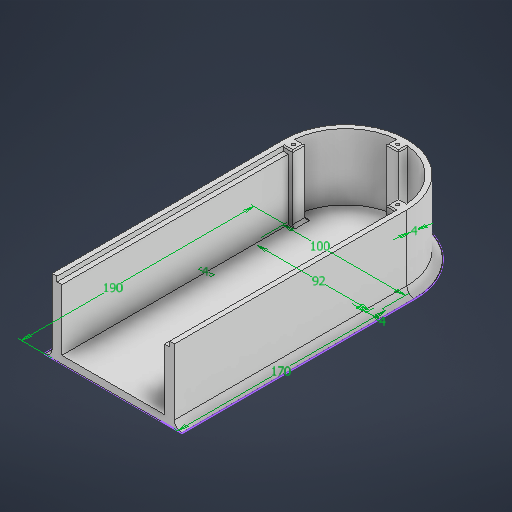
# Autodesk Inventor part: modificacao_manipulador_base
Saved by Autodesk Inventor 2027.1 (Build 311270010, 270A)
## iProperties
Created: 2026-11-03
Part Number: modificacao_manipulador_base
Material: Genérico
Document SubType Name: Modeling
Designer: Evellyn
Density: 1 g/cm^3
Appearance: Padrão
Author: Evellyn
Autodesk Inventor part; units mm, degrees
ref_plane "YZ Plane" through (0, 0, 0) normal (1, 0, 0) x (0, 1, 0)
ref_plane "XZ Plane" through (0, 0, 0) normal (0, 1, 0) x (-1, 0, 0)
ref_plane "XY Plane" through (0, 0, 0) normal (0, 0, 1) x (1, 0, 0)
sketch "Esboço1" plane through (0, 0, 0) normal (0, 1, 0) x (-1, 0, 0)
  line L0 (50.2572, -105.0579) -> (50.2572, 84.9421)
  line L1 (50.2572, 84.9421) -> (-49.7428, 84.9421)
  line L2 (-49.7428, 84.9421) -> (-49.7428, -105.0579)
  line L3 (-49.7428, -85.0579) -> (50.2572, 84.9421) construction
  line L4 (50.2572, -85.0579) -> (-49.7428, 84.9421) construction
  line L5 (50.2572, 0.9229) -> (-49.7428, 0.9229)
  line L6 (-49.7428, 0.9229) -> (-49.7428, -105.0579)
  line L7 (50.2572, -105.0579) -> (50.2572, 0.9229)
  line L8 (0.2572, -0.0579) -> (0.2572, -55.0579)
  arc A0 (-49.7428, -105.0579) -> (50.2572, -105.0579) centre (0.2572, -105.0579) ccw
  line L9 (46.2572, 84.9421) -> (46.2572, -105.0579)
  line L10 (-45.7428, 84.9421) -> (-45.7428, -105.0579)
  arc A1 (-45.7428, -105.0579) -> (46.2572, -105.0579) centre (0.2572, -105.0579) ccw
  line L11 (56.5116, 84.9421) -> (56.5116, -105.0579)
  arc A2 (-55.9972, -105.0579) -> (56.5116, -105.0579) centre (0.2572, -105.0579) ccw
  line L12 (-55.9972, -105.0579) -> (-55.9972, 84.9421)
  line L13 (56.5116, 84.9421) -> (50.2572, 84.9421)
  line L14 (-49.7428, 84.9421) -> (-55.9972, 84.9421)
  dimension "d16" = 170
  dimension "d17" = 100
  dimension "d18" = 4
  dimension "d19" = 190
  dimension "d20" = 4
  dimension "d21" = 4
  dimension "d22" = 92
  constraints: 30 end point, 7 point on circle, 4 point on line, 3 centre point, 3 equal length, 2 horizontal, 2 midpoint, 1 concentric, 1 perpendicular, 1 tangent, 1 vertical, 2 other
  measures "d16" distance of L2.start L3.start
  measures "d17" distance of L3.start L4.start
  measures "d18" distance between parallel lines of L9 L0
  measures "d19" distance of L7.start L0.end
  measures "d20" distance between parallel lines of L6 L10
  measures "d21" radial gap between concentric circles of A1 A0
  measures "d22" distance between parallel lines of L10 L9
extrude "Extrusão1" add sketch "Esboço1" along normal blind 6 contours L9 A1 L10 L5 | L5 L10 L1 L9
extrude "Extrusão2" add sketch "Esboço1" along normal blind 60 contours A0 L2 L5 L10 A1 L9 L0 | L5 L9 L1 L0 | L2 L1 L10 L5
sketch "Esboço2" plane through (0, 6, 0) normal (0, 1, 0) x (1, 0, 0)
  arc A0 (49.7428, 105.0579) -> (-50.2572, 105.0579) centre (-0.2572, 105.0579) ccw projected
  arc A1 (45.7428, 105.0579) -> (-46.2572, 105.0579) centre (-0.2572, 105.0579) ccw projected
  circle A2 centre (-0.2572, 105.0579) radius 48.2336
  line L0 (-0.2572, 155.0579) -> (-0.2572, 49.8481)
  line L1 (-57.3104, 105.0579) -> (74.0886, 105.0579)
  line L2 (45.7428, -84.9421) -> (45.7428, 105.0579) projected
  arc A3 (45.7428, 105.0579) -> (-46.2572, 105.0579) centre (-0.2572, 105.0579) ccw projected
  line L3 (-46.2572, 105.0579) -> (-46.2572, -84.9421) projected
  line L4 (-46.2572, -84.9421) -> (45.7428, -84.9421) projected
  line L5 (4.7428, 153.2919) -> (-5.2572, 153.2919)
  line L6 (-5.2572, 153.2919) -> (-5.2572, 143.2919)
  line L7 (-5.2572, 143.2919) -> (4.7428, 143.2919)
  line L8 (4.7428, 143.2919) -> (4.7428, 153.2919)
  line L9 (4.7428, 153.2919) -> (-5.2572, 143.2919) construction
  line L10 (-5.2572, 153.2919) -> (4.7428, 143.2919) construction
  line L11 (-38.4912, 100.0579) -> (-38.4912, 110.0579)
  line L12 (-48.4912, 100.0579) -> (-38.4912, 100.0579)
  line L13 (-38.4912, 110.0579) -> (-48.4912, 110.0579)
  line L14 (-48.4912, 110.0579) -> (-48.4912, 100.0579)
  line L15 (37.9768, 110.0579) -> (37.9768, 100.0579)
  line L16 (47.9768, 110.0579) -> (37.9768, 110.0579)
  line L17 (37.9768, 100.0579) -> (47.9768, 100.0579)
  line L18 (47.9768, 100.0579) -> (47.9768, 110.0579)
  point P0 (0, 0)
  point P1 (-0.2572, 148.2919)
  point P2 (45.4702, 110.0579)
  point P3 (45.7428, 100.0579)
  point P4 (45.7428, 105.0579)
  point P5 (-45.9847, 110.0579)
  point P6 (-46.2572, 105.0579)
  point P7 (-46.2572, 100.0579)
  point P8 (4.7428, 150.7853)
  point P9 (-5.2572, 150.7853)
  dimension "d27" = 96.4673
  dimension "d32" = 10
  dimension "d33" = 10
  dimension "d34" = 38.234
  dimension "d37" = 180
  constraints: 32 end point, 2 coincident, 2 horizontal, 2 midpoint, 2 parallel, 2 point on line, 1 centre point, 1 perpendicular, 1 point on circle, 1 vertical, 17 other
  measures "d27" diameter of A2
  measures "d32" distance of L7.end L6.end
  measures "d33" distance of L6.end L5.end
  measures "d34" distance from line of A0.centre L7
extrude "Extrusão3" add sketch "Esboço2" along normal blind 54 contours L1 L15 L16 A1 | L2 L17 L15 L1 | L0 L7 L6 A1 | A1 L8 L7 L0 | A1 L13 L11 L1 | L1 L11 L12 L3
fillet "Arredondamento1" radius 1 9 edges at (-5.2572, 60, -147.0386) (4.7428, 60, -147.0386) (-0.2572, 60, -143.2919) (41.8598, 60, -100.0579) (37.9768, 60, -105.0579) (41.7235, 60, -110.0579) (-42.2379, 60, -110.0579) (-42.3742, 60, -100.0579) (-38.4912, 60, -105.0579)
fillet "Arredondamento da face2" radius 2 1 edges at (-38.4912, 6, -105.0579)
fillet "Arredondamento da face3" radius 2 2 edges at (-37.4912, 6, -110.0579) (-42.2379, 6, -110.0579)
fillet "Arredondamento da face4" radius 2 1 edges at (-0.2572, 6, -143.2919)
fillet "Arredondamento da face5" radius 2 2 edges at (4.7428, 6, -142.2919) (4.7428, 6, -147.0386)
fillet "Arredondamento da face6" radius 2 2 edges at (-5.2572, 6, -142.2919) (-5.2572, 6, -147.0386)
fillet "Arredondamento da face7" radius 2 1 edges at (37.9768, 6, -105.0579)
sketch "Esboço3" plane through (0, 6, 0) normal (0, 1, 0) x (1, 0, 0)
  line L0 (-42.2572, 78.0579) -> (-42.2572, -84.9421)
  line L1 (-46.2572, -84.9421) -> (45.7428, -84.9421) projected
  line L2 (-46.2572, -84.9421) -> (-46.2572, 101.0579) projected
  line L3 (37.9768, 100.0579) -> (45.7428, 100.0579) projected
  line L4 (45.7428, 101.0579) -> (45.7428, -84.9421) projected
  line L5 (41.7428, 79.7413) -> (41.7428, -84.9421)
  line L6 (41.7428, 79.7413) -> (41.7428, 100.0579)
  line L7 (-42.2572, 78.0579) -> (-42.2572, 100.0579)
  line L8 (-46.2572, 100.0579) -> (-38.4912, 100.0579) projected
  point P0 (0, 0)
  dimension "d49" = 4
  dimension "d51" = 4
  constraints: 8 end point, 4 point on line, 2 perpendicular, 2 vertical
  measures "d49" distance between parallel lines of L2 L0
  measures "d51" distance between parallel lines of L5 L4
extrude "Extrusão4" add sketch "Esboço3" along normal blind 50
sketch "Esboço4" plane through (0, 60, 0) normal (0, 1, 0) x (1, 0, 0)
  arc A0 (-4.2572, 150.8836) -> (-46.083, 109.0579) centre (-0.2572, 105.0579) ccw projected
  line L0 (-46.083, 109.0579) -> (-39.4912, 109.0579) projected
  line L1 (-39.4912, 109.0579) -> (-39.4912, 101.0579) projected
  line L2 (-39.4912, 101.0579) -> (-46.2572, 101.0579) projected
  line L3 (38.9768, 109.0579) -> (45.5685, 109.0579) projected
  line L4 (38.9768, 101.0579) -> (38.9768, 109.0579) projected
  line L5 (45.7428, 101.0579) -> (38.9768, 101.0579) projected
  arc A1 (45.5685, 109.0579) -> (3.7428, 150.8836) centre (-0.2572, 105.0579) ccw projected
  arc A2 (49.7428, 105.0579) -> (-50.2572, 105.0579) centre (-0.2572, 105.0579) ccw projected
  circle A3 centre (-0.2572, 105.0579) radius 42.5494
  circle A4 centre (-0.2572, 147.6073) radius 1.35
  circle A5 centre (-42.8066, 105.0579) radius 1.35
  circle A6 centre (42.2922, 105.0579) radius 1.35
  point P0 (0, 0)
  dimension "d54" = 85.0988
  dimension "d55" = 2.7
  dimension "d58" = 180
  dimension "d77" = 42.5494
  constraints: 3 centre point, 1 coincident, 1 vertical alignment, 7 other
  measures "d55" diameter of A4
  measures "d77" horizontal distance of A4.centre A6.centre
extrude "Extrusão5" cut sketch "Esboço4" against normal blind 8 contours A4 A3 | A3 A4 | A5 A3 | A3 A5 | A6 A3 | A3 A6
extrude "Extrusão6" add sketch "Esboço1" along normal blind 0.2 contours L0 L13 L11 A2 L12 L14 L2 A0
fillet "Arredondamento da face8" radius 6 1 edges at (49.7428, 0.2, -10.0579)
sketch "Esboço5" plane through (0, 56, 0) normal (0, 1, 0) x (1, 0, 0)
  line L0 (41.7428, -84.9421) -> (45.7428, -84.9421) projected
  line L1 (41.7428, -84.9421) -> (45.7428, -84.9421)
  line L2 (45.7428, -84.9421) -> (45.7428, -64.9421)
  line L3 (45.7428, -64.9421) -> (41.7428, -64.9421)
  line L4 (41.7428, -64.9421) -> (41.7428, -84.9421)
  circle A0 centre (43.7428, -74.9421) radius 1.35
  point P0 (0, 0)
  dimension "d72" = 4
  dimension "d73" = 20
  dimension "d74" = 2.7
  constraints: 8 end point, 2 parallel, 1 centre point, 1 horizontal, 1 perpendicular
  measures "d72" distance of L3.end L2.end
  measures "d73" distance of L2.end L1.end
  measures "d74" diameter of A0
extrude "Extrusão7" cut sketch "Esboço5" against normal blind 6 contours A0
